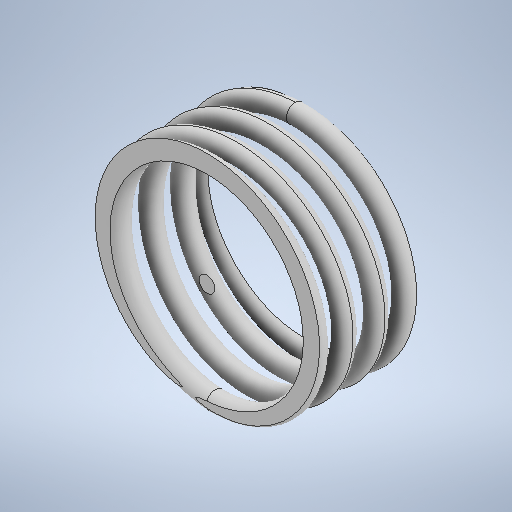
# Autodesk Inventor part: sprezyna
Saved by Autodesk Inventor 2025.2 (Build 292293000, 293)
## iProperties
Created: 2024-12-11
Part Number: sprezyna
Material: Ogólny
Document SubType Name: Modeling
Designer: kajtj
Density: 1 g/cm^3
Appearance: Domyślna
Author: kajtj
Autodesk Inventor part; units mm, degrees
ref_plane "YZ Plane" through (0, 0, 0) normal (1, 0, 0) x (0, 1, 0)
ref_plane "XZ Plane" through (0, 0, 0) normal (0, 1, 0) x (-1, 0, 0)
sketch "Szkic2" plane through (0, 0, 0) normal (1, 0, 0) x (0, 1, 0)
  line L0 (0, 0) -> (0, -33.5) construction
  circle A0 centre (7.5, 0) radius 0.65
  dimension "d0" = 33.5
  dimension "d2" = 1.3
  dimension "d12" = 15
  constraints: 2 end point, 1 centre point, 1 vertical
  measures "d0" distance of L0.start L0.end
  measures "d2" diameter of A0
  measures "d12" diameter of A0.centre L0
coil "Zwój1" sketch "Szkic2" operation add axis through (0, 0, 0) along (0, 0, 1) pitch 2.292 turns 2.5 hand right
sketch "Szkic10" plane through (0, 7.5, 0) normal (1, 0, 0) x (0, 0, -1)
  circle A0 centre (0, 0) radius 0.65 projected
  line L0 (0, 0) -> (0, -15) construction
  line L1 (0, -7.5) -> (5.4293, -7.5) construction
  dimension "d38" = 15
  constraints: 4 end point, 1 horizontal, 1 midpoint, 1 vertical
  measures "d38" distance of L0.start L0.end
coil "Zwój4" sketch "Szkic10" operation add axis through (0, 0, 0) along (0, 0, -1) pitch 1.31 turns 1 hand right
sketch "Szkic11" plane through (0, -7.5, 5.73) normal (1, 0, 0) x (0, 0, -1)
  circle A0 centre (0, 0) radius 0.65 projected
  line L0 (0, 0) -> (0, 15) construction
  line L1 (0, 7.5) -> (-6.9388, 7.5)
  point P0 (0, -0.65)
  dimension "d47" = 15
  constraints: 4 end point, 1 horizontal, 1 midpoint, 1 vertical, 1 vertical alignment
  measures "d47" distance of L0.start L0.end
coil "Zwój5" sketch "Szkic11" operation add axis through (0, 0, 5.73) along (0, 0, 1) pitch 1.31 turns 1 hand right
ref_plane "Płaszczyzna konstrukcyjna1" through (0, -8.15, 5.73) normal (0, -1, 0) x (1, 0, 0)
sketch "Szkic12" plane through (0, -8.15, 5.73) normal (0, -1, 0) x (1, 0, 0)
  line L0 (0, 0.66) -> (0, 1.96) construction
  line L1 (0, -7.69) -> (0, -6.39) construction
  line L2 (9.5411, 5.1902) -> (-9.4647, 5.1902)
  line L3 (9.5411, 0.61) -> (-9.4647, 0.61)
  line L4 (-9.4647, 5.1902) -> (-9.4647, 0.61)
  line L5 (9.5411, 5.1902) -> (9.5411, 0.61)
  point P0 (0, 1.31)
  constraints: 8 end point, 1 horizontal, 1 midpoint, 1 parallel
extrude "Wyciągnięcie proste5" cut sketch "Szkic12" against normal blind 17.5
sketch "Szkic13" plane through (0, -8.15, 5.73) normal (0, -1, 0) x (1, 0, 0)
  line L0 (0, -7.69) -> (0, -6.39) projected
  line L1 (0, -6.39) -> (9.4594, -6.39)
  line L2 (9.4594, -6.39) -> (9.4594, -9.0884)
  line L3 (9.4594, -9.0884) -> (-9.0248, -9.0884)
  line L4 (-9.0248, -9.0884) -> (-9.0248, -6.39)
  line L5 (-9.0248, -6.39) -> (0, -6.39)
  constraints: 10 end point, 4 perpendicular, 1 horizontal, 1 point on line
extrude "Wyciągnięcie proste6" cut sketch "Szkic13" against normal blind 16.75
sketch "Sketch14" plane through (0.063, 0.2901, 6.34) normal (0, 0, 1) x (0.9973, -0.0731, 0)
  circle A0 centre (-0.0416, -0.2939) radius 0.565
  point P0 (-1.2854, -7.6901)
  point P1 (0.4906, -7.55)
  point P2 (0.5234, -7.9978)
  constraints: 1 centre point, 1 coincident, 4 other
extrude "Extrusion7" add sketch "Sketch14" against normal blind 0.0001
